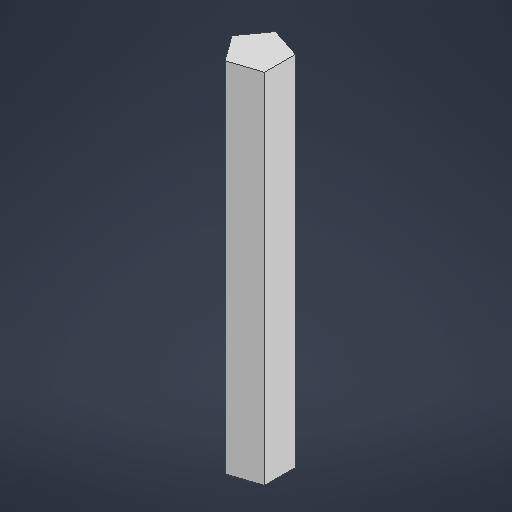
# Autodesk Inventor part: taco
Saved by Autodesk Inventor 2027 (Build 310192060, 192F)
## iProperties
Created: 2026-10-16
Part Number: taco
Material: Generic
Document SubType Name: Modeling
Designer: Pablo
Density: 1 g/cm^3
Appearance: Default
Author: Pablo
Autodesk Inventor part; units mm, degrees
ref_plane "YZ Plane" through (0, 0, 0) normal (1, 0, 0) x (0, 1, 0)
ref_plane "XZ Plane" through (0, 0, 0) normal (0, 1, 0) x (-1, 0, 0)
ref_plane "XY Plane" through (0, 0, 0) normal (0, 0, 1) x (1, 0, 0)
sketch "Sketch2" plane through (0, 0, 0) normal (0, 1, 0) x (-1, 0, 0)
  line L0 (-1.5, 1.0898) -> (0.5729, 1.7634)
  line L1 (0.5729, 1.7634) -> (1.8541, 0)
  line L2 (1.8541, 0) -> (0.5729, -1.7634)
  line L3 (0.5729, -1.7634) -> (-1.5, -1.0898)
  line L4 (-1.5, -1.0898) -> (-1.5, 1.0898)
  point P0 (0, 0)
  point P1 (0, 0)
  point P2 (-1.5, 0)
  dimension "d3" = 1.5
  constraints: 10 end point, 1 coincident, 1 midpoint, 11 other
  measures "d3" distance of point (-1.5, 0) point (0, 0)
extrude "Extrusion2" add sketch "Sketch2" along normal blind 25
body "Solid2"
